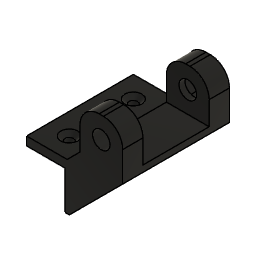
Arm_Corner_Bracket (Autodesk Fusion 360 design; units mm, degrees)
Autodesk Fusion 360 part; units mm, degrees
sketch "Sketch1" plane through (0, 0, 0) normal (0, 0, 1) x (1, 0, 0)
  line L0 (0, 0) -> (45, 0)
  line L1 (45, 0) -> (45, 50)
  line L2 (45, 50) -> (0, 50)
  line L3 (0, 50) -> (0, 0)
  dimension "d1" = 45
  dimension "d2" = 50
  constraint horizontal L0
  constraint vertical L1
  constraint horizontal L2
  constraint vertical L3
  constraint coincident L0.start L3.end
  measures "d1" distance of L1.end L2.end
  measures "d2" distance of L0.end L1.end
extrude "Extrude1" add sketch "Sketch1" along normal blind 4
sketch "Sketch2" plane through (0, 0, 4) normal (0, 0, 1) x (-1, 0, 0)
  line L0 (0, -50) -> (0, 0)
  line L1 (0, 0) -> (-45, 0)
  line L2 (-45, 0) -> (-45, -50)
  line L3 (-45, -50) -> (0, -50)
  circle A0 centre (-10, -40) radius 2
  circle A1 centre (-10, -10) radius 2
  dimension "d5" = 4
  dimension "d6" = 4
  dimension "d7" = 10
  dimension "d8" = 10
  dimension "d9" = 10
  dimension "d10" = 10
  measures "d5" diameter of A0
  measures "d6" diameter of A1
  measures "d7" distance of L0 A0.centre
  measures "d8" distance of L3 A0.centre
  measures "d9" distance of L0 A1.centre
  measures "d10" distance of L1 A1.centre
extrude "Extrude2" cut sketch "Sketch2" against normal blind 4 contours A0 | A1
chamfer "Chamfer1" distance 2 angle 45 2 edges at (11.8647, 39.2768, 4) (11.8647, 9.2768, 4)
sketch "Sketch3" plane through (0, 0, 4) normal (0, 0, 1) x (-1, 0, 0)
  circle A0 centre (-10, -40) radius 4
  line L0 (0, -50) -> (0, 0)
  line L1 (0, 0) -> (-45, 0)
  line L2 (-45, 0) -> (-45, -50)
  line L3 (-45, -50) -> (0, -50)
  circle A1 centre (-10, -10) radius 4
  line L4 (-45, -50) -> (-25, -50)
  line L5 (-25, -50) -> (-25, 0)
  line L6 (-25, 0) -> (-45, 0)
  line L7 (-45, 0) -> (-45, -50)
  dimension "d14" = 20
  constraint horizontal L4
  constraint vertical L5
  constraint horizontal L6
  constraint vertical L7
  constraint coincident L1 L5.end
  constraint coincident L2.end L3.start
  measures "d14" distance of L2.end L4.end
extrude "Extrude3" add sketch "Sketch3" along normal blind 6 contours L1 L2 L3 L4 L5 L6 L7
sketch "Sketch4" plane through (0, 0, 10) normal (0, 0, 1) x (-1, 0, 0)
  line L0 (-45, 0) -> (-45, -50)
  line L1 (-45, -50) -> (-25, -50)
  line L2 (-25, -50) -> (-25, 0)
  line L3 (-25, 0) -> (-45, 0)
  line L4 (-45, -50) -> (-25, -50)
  line L5 (-25, -50) -> (-25, -40.5)
  line L6 (-25, -40.5) -> (-45, -40.5)
  line L7 (-45, -40.5) -> (-45, -50)
  line L8 (-45, 0) -> (-25, 0)
  line L9 (-25, 0) -> (-25, -9.5)
  line L10 (-25, -9.5) -> (-45, -9.5)
  line L11 (-45, -9.5) -> (-45, 0)
  dimension "d18" = 9.5
  dimension "d19" = 9.5
  dimension "d20" = 30
  constraint horizontal L4
  constraint vertical L5
  constraint horizontal L6
  constraint vertical L7
  constraint coincident L2 L5.end
  constraint coincident L0.end L1.start
  constraint horizontal L8
  constraint vertical L9
  constraint horizontal L10
  constraint vertical L11
  constraint coincident L2 L9.end
  constraint coincident L0.start L3.end
  measures "d18" distance of L0.end L6.end
  measures "d19" distance of L0.start L10.end
extrude "Extrude4" add sketch "Sketch4" along normal blind 20 contours L0 L2 L3 L8 L9 L10 L11 | L0 L1 L2 L4 L5 L6 L7
fillet "Fillet1" radius 9 4 edges at (25, 45.25, 30) (45, 45.25, 30) (25, 4.75, 30) (45, 4.75, 30)
sketch "Sketch5" plane through (0, 50, 0) normal (0, 1, 0) x (-1, 0, 0)
  arc A0 (-36, 30) -> (-45, 21) centre (-36, 21) ccw
  line L0 (-45, 21) -> (-45, 0)
  line L1 (-45, 0) -> (0, 0)
  line L2 (0, 0) -> (0, 4)
  line L3 (0, 4) -> (-25, 4)
  line L4 (-25, 4) -> (-25, 21)
  arc A1 (-25, 21) -> (-34, 30) centre (-34, 21) ccw
  line L5 (-34, 30) -> (-36, 30)
  circle A2 centre (-35, 20) radius 4.1
  dimension "d24" = 8.2
  dimension "d25" = 10
  dimension "d26" = 10
  measures "d24" diameter of A2
  measures "d25" distance of L0 A2.centre
  measures "d26" distance of L5 A2.centre
extrude "Extrude5" cut sketch "Sketch5" against normal blind 50 contours A2
sketch "Sketch6" plane through (0, 50, 0) normal (0, 1, 0) x (-1, 0, 0)
  circle A0 centre (-35, 20) radius 4.1
  arc A1 (-36, 30) -> (-45, 21) centre (-36, 21) ccw
  line L0 (-45, 21) -> (-45, 0)
  line L1 (-45, 0) -> (0, 0)
  line L2 (0, 0) -> (0, 4)
  line L3 (0, 4) -> (-25, 4)
  line L4 (-25, 4) -> (-25, 21)
  arc A2 (-25, 21) -> (-34, 30) centre (-34, 21) ccw
  line L5 (-34, 30) -> (-36, 30)
  line L6 (-38.65, 26.3637) -> (-31.35, 26.3637)
  line L7 (-31.35, 26.3637) -> (-27.7, 20.0417)
  line L8 (-27.7, 20.0417) -> (-31.35, 13.7197)
  line L9 (-31.35, 13.7197) -> (-38.65, 13.7197)
  line L10 (-38.65, 13.7197) -> (-42.3, 20.0417)
  line L11 (-42.3, 20.0417) -> (-38.65, 26.3637)
  dimension "d29" = 120
  dimension "d30" = 120
  dimension "d31" = 120
  dimension "d32" = 120
  dimension "d33" = 120
  dimension "d34" = 120
  dimension "d36" = 7.3
  dimension "d37" = 7.3
  dimension "d38" = 7.3
  dimension "d39" = 7.3
  dimension "d40" = 7
  dimension "d41" = 7
  dimension "d42" = 2.7
  dimension "d43" = 3.4551
  constraint perpendicular L4 L6
  constraint parallel L6 L9
  constraint parallel L7 L10
  measures "d29" angle of L6 L11
  measures "d30" angle of L6 L7
  measures "d31" angle of L7 L8
  measures "d32" angle of L8 L9
  measures "d33" angle of L9 L10
  measures "d34" angle of L10 L11
  measures "d36" distance of L6.start L6.end
  measures "d37" distance of L6.end L7.end
  measures "d38" distance of L7.end L8.end
  measures "d39" distance of L8.end L9.end
  measures "d42" distance of L0 L10.end
extrude "Extrude6" cut sketch "Sketch6" against normal blind 6.7 contours L6 L7 L8 L9 L10 L11
sketch "Sketch7" plane through (0, 0, 0) normal (0, 0, -1) x (1, 0, 0)
  circle A0 centre (10, -40) radius 2
  circle A1 centre (10, -10) radius 2
  line L0 (0, 0) -> (0, -50)
  line L1 (0, -50) -> (45, -50)
  line L2 (45, -50) -> (45, 0)
  line L3 (45, 0) -> (0, 0)
  line L4 (45, 0) -> (18, 0)
  line L5 (18, 0) -> (18, -50)
  line L6 (18, -50) -> (45, -50)
  line L7 (45, -50) -> (45, 0)
  dimension "d46" = 18
  constraint horizontal L4
  constraint vertical L5
  constraint horizontal L6
  constraint vertical L7
  constraint coincident L1 L5.end
  constraint coincident L2.end L3.start
  measures "d46" distance of L0 L5
extrude "Extrude7" add sketch "Sketch7" along normal blind 18 contours L1 L2 L3 L4 L5 L6 L7
chamfer "Chamfer2" distance 25 angle 45 1 edges at (45, 25, -18)
chamfer "Chamfer3" distance 6 angle 45 1 edges at (25, 25, 4)
sketch "Sketch8" plane through (18, 0, 0) normal (-1, 0, 0) x (0, -1, 0)
  line L0 (0, 0) -> (-50, 0)
  line L1 (-50, 0) -> (-50, -18)
  line L2 (-50, -18) -> (0, -18)
  line L3 (0, -18) -> (0, 0)
  circle A0 centre (-25, -9) radius 2
  dimension "d51" = 4
  dimension "d52" = 25
  dimension "d53" = 9
  measures "d51" diameter of A0
  measures "d52" distance of L1 A0.centre
  measures "d53" distance of L2 A0.centre
extrude "Extrude8" cut sketch "Sketch8" against normal blind 18 contours A0
sketch "Sketch9" plane through (45, 0, 0) normal (1, 0, 0) x (0, 1, 0)
  line L0 (0, 7) -> (50, 7)
  line L1 (50, 7) -> (50, 21)
  line L2 (50, 21) -> (40.5, 21)
  line L3 (40.5, 21) -> (40.5, 10)
  line L4 (40.5, 10) -> (9.5, 10)
  line L5 (9.5, 10) -> (9.5, 21)
  line L6 (9.5, 21) -> (0, 21)
  line L7 (0, 21) -> (0, 7)
  circle A0 centre (25, -9) radius 3.5
  dimension "d58" = 7
  measures "d58" diameter of A0
extrude "Extrude9" cut sketch "Sketch9" against normal blind 19 contours A0
